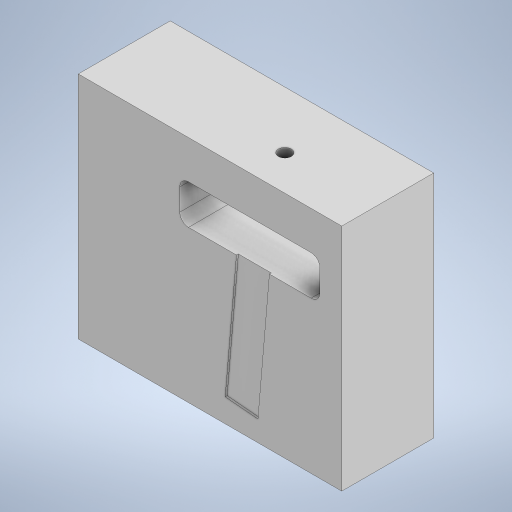
# Autodesk Inventor part: snail_coffin_cavity_bottom
Saved by Autodesk Inventor 2024.3 (Build 283343000, 343)
## iProperties
Created: 2024-06-10
Part Number: snail_coffin_cavity_bottom
Material: Generic
Document SubType Name: Modeling
Designer: ajb
Density: 1 g/cm^3
Appearance: Default
d0: 4.500 mm
d1: 16.000 mm
d2: 32.000 mm
d3: 9.000 mm
d4: 2.000 mm
d5: 85.00 deg
d6: 2.650 mm
d7: 4.850 mm
d8: 34.750 mm
d9: 0.565 mm
d11: 13.250 mm
d12: 21.000 mm
d13: 39.185 mm
d14: 39.185 mm
d15: 21.000 mm
d16: 0.00 deg
d17: 16.000 mm
d18: 0.00 deg
d19: 0.430 mm
d20: 0.00 deg
d21: 8.000 mm
d22: 2.946 mm
d27: 8.750 mm
d28: 118.00 deg
cavity_x: 32.000 mm
cavity_y: 9.000 mm
cavity_z: 32.000 mm
chip_length: 34.750 mm
chip_width: 7.500 mm
chip_thickness: 0.430 mm
chip_delta_x_neg: 2.250 mm
chip_delta_x_pos: 4.450 mm
chip_delta_y_neg: 0.000 mm
chip_delta_y_pos: 0.565 mm
theta: 85.00 deg
flux_loop_length: 8.105 mm
flux_loop_width: 1.000 mm
sma_port_length: 8.750 mm
sma_port_diameter: 2.946 mm
seam_width: 1.200 mm
flux_delta_x_neg: 0.050 mm
flux_delta_x_pos: 0.950 mm
d10: 7.500 mm
chip_padding: 0.400 mm
padding: 5.000 mm
flux_loop_padding: 0.430 mm
Author: ajb
Autodesk Inventor part; units mm, degrees
ref_plane "YZ Plane" through (0, 0, 0) normal (1, 0, 0) x (0, 1, 0)
ref_plane "XZ Plane" through (0, 0, 0) normal (0, 1, 0) x (-1, 0, 0)
ref_plane "XY Plane" through (0, 0, 0) normal (0, 0, 1) x (1, 0, 0)
sketch "Sketch1" plane through (0, 0, 0) normal (0, 0, 1) x (1, 0, 0)
  line L0 (-14, 4.5) -> (14, 4.5)
  line L1 (16, 2.5) -> (16, -2.5)
  line L2 (14, -4.5) -> (-14, -4.5)
  line L3 (-16, -2.5) -> (-16, 2.5)
  arc A0 (-14, 4.5) -> (-16, 2.5) centre (-14, 2.5) ccw
  arc A1 (-16, -2.5) -> (-14, -4.5) centre (-14, -2.5) ccw
  arc A2 (16, 2.5) -> (14, 4.5) centre (14, 2.5) ccw
  arc A3 (14, -4.5) -> (16, -2.5) centre (14, -2.5) ccw
  point P0 (0, 0)
  point P1 (16, -4.5)
  point P2 (16, 4.5)
  point P3 (-16, -4.5)
  dimension "d0" = 4.5
  dimension "d1" = 16
  dimension "d2" = 32
  dimension "d3" = 9
  dimension "d4" = 2
  constraints: 8 end point, 8 point on circle, 8 tangent, 6 point on line, 4 centre point, 3 equal radius, 2 parallel, 1 horizontal, 1 perpendicular
  measures "d0" distance from line of L0 point (0, 0)
  measures "d1" distance from line of L1 point (0, 0)
  measures "d2" distance of point (16, -4.5) point (-16, -4.5)
  measures "d3" distance of point (16, 4.5) point (16, -4.5)
  measures "d4" radius of A0
sketch "Sketch2" plane through (0, 0, 0) normal (0, 0, 1) x (1, 0, 0)
  line L0 (0, 0) -> (0.0492, 0.5629)
  line L1 (0, 0) -> (0.565, 0) construction
  line L2 (0.0492, 0.5629) -> (4.8808, 0.1401)
  line L3 (4.8808, 0.1401) -> (1.8521, -34.4776)
  line L4 (1.8521, -34.4776) -> (-5.6193, -33.824)
  line L5 (-5.6193, -33.824) -> (-2.5907, 0.7938)
  line L6 (-2.5907, 0.7938) -> (0.0492, 0.5629)
  dimension "d5" = 85
  dimension "d6" = 2.65
  dimension "d7" = 4.85
  dimension "d8" = 34.75
  dimension "d9" = 0.565
  dimension "d10" = 7.5
  constraints: 14 end point, 5 perpendicular, 1 equal length, 1 horizontal, 1 point on line
  measures "d5" angle of L1 L0
  measures "d6" distance from line of L5 L0.start
  measures "d7" distance from line of L3 L0.start
  measures "d8" distance from line of L4 L0.end
  measures "d9" distance from line of L2 L0.start
  measures "d10" distance between parallel lines of L3 L5
sketch "Sketch3" plane through (0, 0, 0) normal (0, 0, 1) x (1, 0, 0)
  line L0 (-39.185, 13.25) -> (21, 13.25)
  line L1 (21, 13.25) -> (21, -39.185)
  line L2 (21, -39.185) -> (-39.185, -39.185)
  line L3 (-39.185, -39.185) -> (-39.185, 13.25)
  point P0 (0, 0)
  dimension "d11" = 13.25
  dimension "d12" = 21
  dimension "d13" = 39.185
  dimension "d14" = 39.185
  constraints: 8 end point, 2 parallel, 1 horizontal, 1 perpendicular
  measures "d11" distance from line of L0 point (0, 0)
  measures "d12" distance from line of L1 point (0, 0)
  measures "d13" distance from line of L2 point (0, 0)
  measures "d14" distance from line of L3 point (0, 0)
extrude "Extrusion1" add sketch "Sketch3" against normal blind 21
extrude "Extrusion2" cut sketch "Sketch1" against normal blind 16
extrude "Extrusion3" cut sketch "Sketch2" against normal blind 0.43
sketch "Sketch4" plane through (-39.185, 13.25, 0) normal (0, 1, 0) x (1, 0, 0)
  point P0 (39.185, 0)
  point P1 (39.185, 8)
  dimension "d21" = 8
  measures "d21" distance of point (39.185, 8) point (39.185, 0)
hole "Hole1" at (0, 13.25, -8) direction (0, -1, 0) diameter 2.946 depth 8.75 tip angle 118
sketch "Sketch5" plane through (0, 0, 0) normal (0, 0, 1) x (1, 0, 0)
  line L0 (-14, 5.7) -> (14, 5.7)
  line L1 (16, 3.7) -> (16, -3.7)
  line L2 (14, -5.7) -> (-14, -5.7)
  line L3 (-16, -3.7) -> (-16, 3.7)
  arc A0 (-14, 5.7) -> (-16, 3.7) centre (-14, 3.7) ccw
  arc A1 (16, 3.7) -> (14, 5.7) centre (14, 3.7) ccw
  arc A2 (14, -5.7) -> (16, -3.7) centre (14, -3.7) ccw
  arc A3 (-16, -3.7) -> (-14, -5.7) centre (-14, -3.7) ccw
  point P0 (0, 0)
  point P1 (-16, 5.7)
  point P2 (16, 5.7)
  point P3 (-16, -5.7)
  dimension "d29" = 5.7
  dimension "d30" = 16
  dimension "d31" = 32
  dimension "d32" = 11.4
  dimension "d33" = 2
  constraints: 8 end point, 8 point on circle, 8 tangent, 6 point on line, 4 centre point, 3 equal radius, 2 parallel, 1 horizontal, 1 perpendicular
  measures "d29" distance from line of L0 point (0, 0)
  measures "d30" distance from line of L3 point (0, 0)
  measures "d31" distance of point (-16, 5.7) point (16, 5.7)
  measures "d32" distance of point (-16, -5.7) point (-16, 5.7)
  measures "d33" radius of A0
equation "\"d0\" = 0.5 * cavity_y"
equation "\"d1\" = 0.5 * cavity_x"
equation "\"d2\" = cavity_x"
equation "\"d3\" = cavity_y"
equation "\"d5\" = theta"
equation "\"d8\" = chip_length"
equation "\"d9\" = chip_delta_y_pos"
equation "\"d11\" = 0.5 * cavity_y + sma_port_length"
equation "\"d12\" = 0.5 * cavity_x + padding"
equation "\"d13\" = -chip_delta_y_pos + chip_length + padding"
equation "\"d14\" = -chip_delta_y_pos + chip_length + padding"
equation "\"d15\" = 0.5 * cavity_z + padding"
equation "\"d17\" = 0.5 * cavity_z"
equation "\"d19\" = chip_thickness"
equation "\"d21\" = 0.25 * cavity_z"
equation "\"d22\" = sma_port_diameter"
equation "\"d27\" = sma_port_length"
equation "\"d29\" = 0.5 * cavity_y + seam_width"
equation "\"d30\" = 0.5 * cavity_x"
equation "\"d31\" = cavity_x"
equation "\"d32\" = cavity_y + 2 * seam_width"
equation "\"cavity_x\" = 32"
equation "\"cavity_y\" = 9"
equation "\"cavity_z\" = 32"
equation "\"chip_length\" = 34.75"
equation "\"chip_width\" = 7.5"
equation "\"chip_thickness\" = 0.43"
equation "\"chip_delta_x_neg\" = 2.25"
equation "\"chip_delta_x_pos\" = 4.45"
equation "\"chip_delta_y_neg\" = 0"
equation "\"chip_delta_y_pos\" = 0.565"
equation "\"theta\" = 85deg"
equation "\"flux_loop_length\" = 8.105"
equation "\"flux_loop_width\" = 1"
equation "\"flux_loop_padding\" = 0.43"
equation "\"sma_port_length\" = 8.75"
equation "\"sma_port_diameter\" = 2.946"
equation "\"seam_width\" = 1.2"
equation "\"padding\" = 5"
equation "\"flux_delta_x_neg\" = 0.05"
equation "\"flux_delta_x_pos\" = 0.95"
equation "\"chip_padding\" = 0.4"
body "Solid1"
